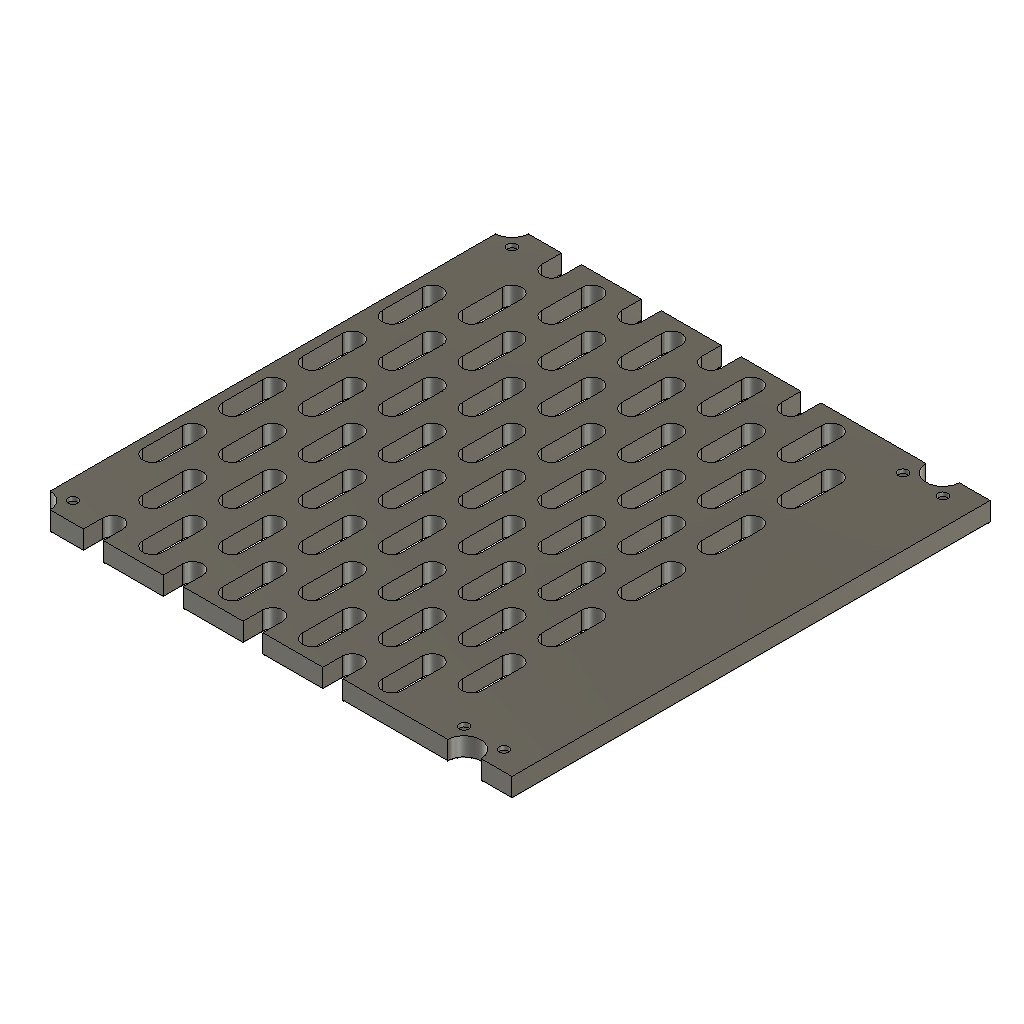
panel-right-edge-v03 (Autodesk Fusion 360 design; units mm, degrees)
part number: 2026-10-27-17-32-11-487
part number: 2026-10-27-17-32-12-104
Autodesk Fusion 360 part; units mm, degrees
sketch "01 Panel blank sketch" plane through (0, 0, 0) normal (0, 0, 1) x (1, 0, 0) in component "Panel right-edge"
  line L0 (0.1, 0.1) -> (119.9, 0.1)
  line L1 (119.9, 0.1) -> (119.9, 119.9)
  line L2 (119.9, 119.9) -> (0.1, 119.9)
  line L3 (0.1, 119.9) -> (0.1, 0.1)
  dimension "d57" = 0.1
  dimension "d58" = 0.1
  dimension "d59" = 119.8
  dimension "d60" = 119.8
  constraint horizontal L0
  constraint vertical L1
  constraint horizontal L2
  constraint vertical L3
  measures "d57" horizontal distance of origin L0.start
  measures "d58" vertical distance of origin L0.start
  measures "d59" horizontal distance of L0.start L0.end
  measures "d60" vertical distance of L0.end L1.end
extrude "01 Panel blank" add sketch "01 Panel blank sketch" along normal blind 5 in component "Panel right-edge"
sketch "03 A main constrained seed" plane through (0, 0, 0) normal (0, 0, 1) x (1, 0, 0) in component "Panel right-edge"
  line L0 (27.5, 5) -> (27.5, 15)
  arc A0 (27.5, 15) -> (22.5, 15) centre (25, 15) ccw
  line L1 (22.5, 15) -> (22.5, 5)
  arc A1 (22.5, 5) -> (27.5, 5) centre (25, 5) ccw
  line L2 (25, 5) -> (25, 15) construction
  line L3 (25, 5) -> (35, 5) construction
  dimension "d63" = 5
  dimension "d64" = 10
  dimension "d65" = 90
  dimension "d66" = 10
  dimension "d67" = 25
  dimension "d68" = 5
  constraint tangent L0 A0
  constraint tangent A0 L1
  constraint tangent L1 A1
  constraint tangent L0 A1
  constraint parallel L0 L1
  constraint horizontal L3
  measures "d63" diameter of A0
  measures "d64" distance of A1.centre A0.centre
  measures "d65" angle of L2 L3
  measures "d66" horizontal distance of A1.centre L3.end
  measures "d67" horizontal distance of origin A1.centre
  measures "d68" vertical distance of origin A1.centre
extrude "03 A main through cut" cut sketch "03 A main constrained seed" along normal blind 5 in component "Panel right-edge"
pattern_linear "03 A main lattice" count 4 spacing 20 along (1, 0, 0) count 6 spacing 20 along (0, 1, 0) of "03 A main through cut" in component "Panel right-edge"
sketch "04 A end strip constrained seed" plane through (0, 0, 0) normal (0, 0, 1) x (1, 0, 0) in component "Panel right-edge"
  line L0 (7.5, 25) -> (7.5, 35)
  arc A0 (7.5, 35) -> (2.5, 35) centre (5, 35) ccw
  line L1 (2.5, 35) -> (2.5, 25)
  arc A1 (2.5, 25) -> (7.5, 25) centre (5, 25) ccw
  line L2 (5, 25) -> (5, 35) construction
  line L3 (5, 25) -> (15, 25) construction
  dimension "d75" = 5
  dimension "d76" = 10
  dimension "d77" = 90
  dimension "d78" = 10
  dimension "d79" = 5
  dimension "d80" = 25
  constraint tangent L0 A0
  constraint tangent A0 L1
  constraint tangent L1 A1
  constraint tangent L0 A1
  constraint parallel L0 L1
  constraint horizontal L3
  measures "d75" diameter of A0
  measures "d76" distance of A1.centre A0.centre
  measures "d77" angle of L2 L3
  measures "d78" horizontal distance of A1.centre L3.end
  measures "d79" horizontal distance of origin A1.centre
  measures "d80" vertical distance of origin A1.centre
extrude "04 A end strip through cut" cut sketch "04 A end strip constrained seed" along normal blind 5 in component "Panel right-edge"
pattern_linear "04 A end strip lattice" count 1 spacing 20 along (1, 0, 0) count 4 spacing 20 along (0, 1, 0) of "04 A end strip through cut" in component "Panel right-edge"
sketch "05 B main constrained seed" plane through (0, 0, 0) normal (0, 0, 1) x (1, 0, 0) in component "Panel right-edge"
  line L0 (17.5, -5) -> (17.5, 5)
  arc A0 (17.5, 5) -> (12.5, 5) centre (15, 5) ccw
  line L1 (12.5, 5) -> (12.5, -5)
  arc A1 (12.5, -5) -> (17.5, -5) centre (15, -5) ccw
  line L2 (15, -5) -> (15, 5) construction
  line L3 (15, -5) -> (25, -5) construction
  dimension "d87" = 5
  dimension "d88" = 10
  dimension "d89" = 90
  dimension "d90" = 10
  dimension "d91" = 15
  dimension "d92" = 5
  constraint tangent L0 A0
  constraint tangent A0 L1
  constraint tangent L1 A1
  constraint tangent L0 A1
  constraint parallel L0 L1
  constraint horizontal L3
  measures "d87" diameter of A0
  measures "d88" distance of A1.centre A0.centre
  measures "d89" angle of L2 L3
  measures "d90" horizontal distance of A1.centre L3.end
  measures "d91" horizontal distance of origin A1.centre
  measures "d92" vertical distance of origin A1.centre
extrude "05 B main through cut" cut sketch "05 B main constrained seed" along normal blind 5 in component "Panel right-edge"
pattern_linear "05 B main lattice" count 4 spacing 20 along (1, 0, 0) count 7 spacing 20 along (0, 1, 0) of "05 B main through cut" in component "Panel right-edge"
sketch "06 B end strip constrained seed" plane through (0, 0, 0) normal (0, 0, 1) x (1, 0, 0) in component "Panel right-edge"
  line L0 (97.5, 15) -> (97.5, 25)
  arc A0 (97.5, 25) -> (92.5, 25) centre (95, 25) ccw
  line L1 (92.5, 25) -> (92.5, 15)
  arc A1 (92.5, 15) -> (97.5, 15) centre (95, 15) ccw
  line L2 (95, 15) -> (95, 25) construction
  line L3 (95, 15) -> (105, 15) construction
  dimension "d99" = 5
  dimension "d100" = 10
  dimension "d101" = 90
  dimension "d102" = 10
  dimension "d103" = 95
  dimension "d104" = 15
  constraint tangent L0 A0
  constraint tangent A0 L1
  constraint tangent L1 A1
  constraint tangent L0 A1
  constraint parallel L0 L1
  constraint horizontal L3
  measures "d99" diameter of A0
  measures "d100" distance of A1.centre A0.centre
  measures "d101" angle of L2 L3
  measures "d102" horizontal distance of A1.centre L3.end
  measures "d103" horizontal distance of origin A1.centre
  measures "d104" vertical distance of origin A1.centre
extrude "06 B end strip through cut" cut sketch "06 B end strip constrained seed" along normal blind 5 in component "Panel right-edge"
pattern_linear "06 B end strip lattice" count 1 spacing 20 along (1, 0, 0) count 5 spacing 20 along (0, 1, 0) of "06 B end strip through cut" in component "Panel right-edge"
sketch "07 Shared node clearance sketch" plane through (0, 0, 0) normal (0, 0, 1) x (1, 0, 0) in component "Panel right-edge"
  circle A0 centre (0, 0) radius 4.2
  dimension "d111" = 8.4
  constraint coincident A0.centre origin
  measures "d111" diameter of A0
extrude "07 Shared node clearance" cut sketch "07 Shared node clearance sketch" along normal blind 5 in component "Panel right-edge"
sketch "07 Shared node clearance sketch (1)" plane through (0, 0, 0) normal (0, 0, 1) x (1, 0, 0) in component "Panel right-edge"
  circle A0 centre (0, 120) radius 4.2
  dimension "d114" = 120
  dimension "d115" = 8.4
  constraint vertical origin A0.centre
  measures "d114" vertical distance of origin A0.centre
  measures "d115" diameter of A0
extrude "07 Shared node clearance (1)" cut sketch "07 Shared node clearance sketch (1)" along normal blind 5 in component "Panel right-edge"
sketch "07 Shared node clearance sketch (2)" plane through (0, 0, 0) normal (0, 0, 1) x (1, 0, 0) in component "Panel right-edge"
  circle A0 centre (108, 0) radius 4.2
  dimension "d118" = 108
  dimension "d119" = 8.4
  constraint horizontal origin A0.centre
  measures "d118" horizontal distance of origin A0.centre
  measures "d119" diameter of A0
extrude "07 Shared node clearance (2)" cut sketch "07 Shared node clearance sketch (2)" along normal blind 5 in component "Panel right-edge"
sketch "07 Shared node clearance sketch (3)" plane through (0, 0, 0) normal (0, 0, 1) x (1, 0, 0) in component "Panel right-edge"
  circle A0 centre (108, 120) radius 4.2
  dimension "d122" = 108
  dimension "d123" = 120
  dimension "d124" = 8.4
  measures "d122" horizontal distance of origin A0.centre
  measures "d123" vertical distance of origin A0.centre
  measures "d124" diameter of A0
extrude "07 Shared node clearance (3)" cut sketch "07 Shared node clearance sketch (3)" along normal blind 5 in component "Panel right-edge"
fillet "08 Rounded slot entrances and face edges" radius 0.4 2 faces at (112.4333, 58.3333, 0) (112.4333, 58.3333, 0) in component "Panel right-edge"
ref_plane "WorkPlane1" through (0, 0, 5) normal (0, 0, 1) x (1, 0, 0) in component "Panel right-edge"
sketch "09 Blind rear key socket sketch" plane through (0, 0, 5) normal (0, 0, 1) x (1, 0, 0) in component "Panel right-edge"
  circle A0 centre (5, 80) radius 1.7
  dimension "d131" = 5
  dimension "d132" = 80
  dimension "d133" = 3.4
  measures "d131" horizontal distance of origin A0.centre
  measures "d132" vertical distance of origin A0.centre
  measures "d133" diameter of A0
ref_plane "WorkPlane2" through (0, 0, 5) normal (0, 0, 1) x (1, 0, 0) in component "Panel right-edge"
sketch "09 Blind rear key socket sketch (1)" plane through (0, 0, 5) normal (0, 0, 1) x (1, 0, 0) in component "Panel right-edge"
  circle A0 centre (70, 5) radius 1.7
  dimension "d138" = 70
  dimension "d139" = 5
  dimension "d140" = 3.4
  measures "d138" horizontal distance of origin A0.centre
  measures "d139" vertical distance of origin A0.centre
  measures "d140" diameter of A0
ref_plane "WorkPlane3" through (0, 0, 5) normal (0, 0, 1) x (1, 0, 0) in component "Panel right-edge"
sketch "09 Blind rear key socket sketch (2)" plane through (0, 0, 5) normal (0, 0, 1) x (1, 0, 0) in component "Panel right-edge"
  circle A0 centre (70, 115) radius 1.7
  dimension "d145" = 70
  dimension "d146" = 115
  dimension "d147" = 3.4
  measures "d145" horizontal distance of origin A0.centre
  measures "d146" vertical distance of origin A0.centre
  measures "d147" diameter of A0
ref_plane "WorkPlane4" through (0, 0, 5) normal (0, 0, 1) x (1, 0, 0) in component "Panel right-edge"
sketch "10 Node register socket sketch" plane through (0, 0, 5) normal (0, 0, 1) x (1, 0, 0) in component "Panel right-edge"
  circle A0 centre (5, 5) radius 1.2
  dimension "d152" = 5
  dimension "d153" = 5
  dimension "d154" = 2.4
  measures "d152" horizontal distance of origin A0.centre
  measures "d153" vertical distance of origin A0.centre
  measures "d154" diameter of A0
extrude "10 Node register socket" cut sketch "10 Node register socket sketch" against normal blind 1 in component "Panel right-edge"
ref_plane "WorkPlane5" through (0, 0, 5) normal (0, 0, 1) x (1, 0, 0) in component "Panel right-edge"
sketch "10 Node register socket sketch (1)" plane through (0, 0, 5) normal (0, 0, 1) x (1, 0, 0) in component "Panel right-edge"
  circle A0 centre (5, 115) radius 1.2
  dimension "d159" = 5
  dimension "d160" = 115
  dimension "d161" = 2.4
  measures "d159" horizontal distance of origin A0.centre
  measures "d160" vertical distance of origin A0.centre
  measures "d161" diameter of A0
extrude "10 Node register socket (1)" cut sketch "10 Node register socket sketch (1)" against normal blind 1 in component "Panel right-edge"
ref_plane "WorkPlane6" through (0, 0, 5) normal (0, 0, 1) x (1, 0, 0) in component "Panel right-edge"
sketch "10 Node register socket sketch (2)" plane through (0, 0, 5) normal (0, 0, 1) x (1, 0, 0) in component "Panel right-edge"
  circle A0 centre (103, 5) radius 1.2
  dimension "d166" = 103
  dimension "d167" = 5
  dimension "d168" = 2.4
  measures "d166" horizontal distance of origin A0.centre
  measures "d167" vertical distance of origin A0.centre
  measures "d168" diameter of A0
extrude "10 Node register socket (2)" cut sketch "10 Node register socket sketch (2)" against normal blind 1 in component "Panel right-edge"
ref_plane "WorkPlane7" through (0, 0, 5) normal (0, 0, 1) x (1, 0, 0) in component "Panel right-edge"
sketch "10 Node register socket sketch (3)" plane through (0, 0, 5) normal (0, 0, 1) x (1, 0, 0) in component "Panel right-edge"
  circle A0 centre (113, 5) radius 1.2
  dimension "d173" = 113
  dimension "d174" = 5
  dimension "d175" = 2.4
  measures "d173" horizontal distance of origin A0.centre
  measures "d174" vertical distance of origin A0.centre
  measures "d175" diameter of A0
extrude "10 Node register socket (3)" cut sketch "10 Node register socket sketch (3)" against normal blind 1 in component "Panel right-edge"
ref_plane "WorkPlane8" through (0, 0, 5) normal (0, 0, 1) x (1, 0, 0) in component "Panel right-edge"
sketch "10 Node register socket sketch (4)" plane through (0, 0, 5) normal (0, 0, 1) x (1, 0, 0) in component "Panel right-edge"
  circle A0 centre (103, 115) radius 1.2
  dimension "d180" = 103
  dimension "d181" = 115
  dimension "d182" = 2.4
  measures "d180" horizontal distance of origin A0.centre
  measures "d181" vertical distance of origin A0.centre
  measures "d182" diameter of A0
extrude "10 Node register socket (4)" cut sketch "10 Node register socket sketch (4)" against normal blind 1 in component "Panel right-edge"
ref_plane "WorkPlane9" through (0, 0, 5) normal (0, 0, 1) x (1, 0, 0) in component "Panel right-edge"
sketch "10 Node register socket sketch (5)" plane through (0, 0, 5) normal (0, 0, 1) x (1, 0, 0) in component "Panel right-edge"
  circle A0 centre (113, 115) radius 1.2
  dimension "d187" = 113
  dimension "d188" = 115
  dimension "d189" = 2.4
  measures "d187" horizontal distance of origin A0.centre
  measures "d188" vertical distance of origin A0.centre
  measures "d189" diameter of A0
extrude "10 Node register socket (5)" cut sketch "10 Node register socket sketch (5)" against normal blind 1 in component "Panel right-edge"
component "Panel right-edge" placed x (1, 0, 0) y (0, 1, 0) z (0, 0, 1) at (0, 0, 0)
equation "columns = 6" comment "Even integer 4..14; each cell is 20 mm"
equation "rows = 6" comment "Even integer 4..14"
equation "pitch = 20 mm" comment "Keep for dense SKADIS compatible lattice"
equation "panelWidth = columns * pitch" comment "Nominal module pitch X"
equation "panelHeight = rows * pitch" comment "Nominal module pitch Y"
equation "seamGap = 0.2 mm" comment "Physical envelope shrinks around fixed lattice"
equation "boardThickness = 5 mm" comment "Fit-test with real hooks"
equation "slotWidth = 5 mm" comment "Minimum throat width"
equation "slotHeight = 15 mm" comment "Minimum throat height"
equation "entryRadius = 0.4 mm" comment "Front slot and perimeter edge rounding"
equation "cornerRadius = 6 mm" comment "Plan-view panel corner rounding"
equation "hookClearance = 10 mm" comment "PROVISIONAL: board rear to front of extrusion"
equation "frameZ = boardThickness + hookClearance" comment "Front extrusion datum"
equation "mountInset = 12 mm" comment "Exterior node inset from outside module edge"
equation "mountBore = 8.4 mm" comment "Clearance around 8 mm metal shoulder"
equation "capDiameter = 18 mm" comment "Visible decorative mounting disk"
equation "capThickness = 5 mm" comment "Metal clamping cap / washer"
equation "seatThickness = 2 mm" comment "Printed rear bearing washer"
equation "screwDiameter = 5 mm" comment "Nominal M5 reference, threads omitted"
equation "screwClearance = 5.5 mm" comment "Cap and spacer bore"
equation "keyWidth = 4 mm" comment "Registration key corridor width"
equation "keyThickness = 2 mm" comment "Rear removable key body"
equation "keyPegDiameter = 3 mm" comment "Rear locating peg"
equation "keySocketDiameter = 3.4 mm" comment "0.2 mm radial starting fit"
equation "keyPegHeight = 0.8 mm" comment "Peg penetration"
equation "keySocketDepth = 1 mm" comment "Blind locating pocket"
equation "profileMouth = 6.28 mm" comment "User measured mouth"
equation "profileCavity = 11 mm" comment "User measured widest cavity"
equation "profileDepth = 6.2 mm" comment "User measured face-to-floor depth"
equation "profileFloor = 5.7 mm" comment "User estimate, lower confidence"
equation "profileLip = 1.5 mm" comment "Unmeasured; tentative comparable catalog value"
equation "profileTaperStart = profileDepth - ( profileCavity - profileFloor ) / 2" comment "Assumed 45-degree inner slopes"
equation "profileBore = 5 mm" comment "Unmeasured central bore, reference only"
equation "nutWidth = 8.8 mm" comment "Provisional low-profile METAL T-nut envelope, not old rectangular carrier"
equation "nutLength = 12 mm" comment "End-loaded anti-rotation metal nut envelope"
equation "nutThickness = 2.7 mm" comment "Thin nut reference; fit/load still unverified"
equation "jointLeg = 18 mm" comment "In-bay angle footprint"
equation "jointThickness = 3 mm" comment "Metal bracket thickness"
equation "jointDepth = 16 mm" comment "Bracket depth within 20 mm rail"
equation "sideScrewLength = 8 mm" comment "M5x8 reference; check against actual bracket and nut"
equation "registerPin = 2 mm" comment "Node-seat locating pins"
equation "registerSocket = 2.4 mm" comment "Starting printed locating clearance"
equation "registerPinHeight = 0.8 mm" comment "Pin into rear socket"
equation "registerSocketDepth = 1 mm" comment "Blind panel socket"
equation "registerOffset = 5 mm" comment "Four pegs at node +/- offset"
equation "wallTabHeight = 24 mm" comment "Tab along extrusion"
equation "wallTabReach = 22 mm" comment "Tab into open bay"
equation "wallAnchorClearance = 6.5 mm" comment "Placeholder wall anchor interface"
equation "wallShim = 0 mm" comment "Only actual leveling shims; no designed rear air gap"
equation "wallDriverDiameter = 12 mm" comment "Clear tool envelope in open bays"
equation "keyDriverDiameter = 5 mm" comment "Short hex-key working-leg envelope"
equation "keyDriverReach = 20 mm" comment "Short hex-key working-leg reach"
equation "panelLeft = 0" comment "0 internal / 1 finished; full cell border and inset mounting"
equation "panelRight = 1" comment "0 internal / 1 finished; full cell border and inset mounting"
equation "panelBottom = 0" comment "0 internal / 1 finished; full cell border and inset mounting"
equation "panelTop = 0" comment "0 internal / 1 finished; full cell border and inset mounting"
equation "d57 = abs(( 0 mm ) + seamGap / 2)"
equation "d58 = abs(( 0 mm ) + seamGap / 2)"
equation "d59 = panelWidth - seamGap"
equation "d60 = panelHeight - seamGap"
equation "d61 = boardThickness"
equation "d63 = slotWidth"
equation "d64 = slotHeight - slotWidth"
equation "d66 = pitch / 2"
equation "d67 = abs(( 0 mm ) + pitch / 4 + pitch * ( panelLeft + 1 ))"
equation "d68 = abs(( ( 0 mm ) + pitch / 2 + pitch * panelBottom ) - ( slotHeight - slotWidth ) / 2)"
equation "d69 = boardThickness"
equation "d71 = columns - panelLeft - panelRight - 1"
equation "d72 = rows - panelBottom - panelTop"
equation "d73 = pitch"
equation "d74 = pitch"
equation "d75 = slotWidth"
equation "d76 = slotHeight - slotWidth"
equation "d78 = pitch / 2"
equation "d79 = abs(( 0 mm ) + pitch / 4 + pitch * panelLeft)"
equation "d80 = abs(( ( 0 mm ) + 3 * pitch / 2 + pitch * panelBottom ) - ( slotHeight - slotWidth ) / 2)"
equation "d81 = boardThickness"
equation "d84 = rows - panelBottom - panelTop - 2"
equation "d85 = pitch"
equation "d86 = pitch"
equation "d87 = slotWidth"
equation "d88 = slotHeight - slotWidth"
equation "d90 = pitch / 2"
equation "d91 = abs(( 0 mm ) + 3 * pitch / 4 + pitch * panelLeft)"
equation "d92 = abs(( ( 0 mm ) + pitch * panelBottom ) - ( slotHeight - slotWidth ) / 2)"
equation "d93 = boardThickness"
equation "d95 = columns - panelLeft - panelRight - 1"
equation "d96 = rows + 1 - panelBottom - panelTop"
equation "d97 = pitch"
equation "d98 = pitch"
equation "d99 = slotWidth"
equation "d100 = slotHeight - slotWidth"
equation "d102 = pitch / 2"
equation "d103 = abs(( 0 mm ) + panelWidth - pitch / 4 - pitch * panelRight)"
equation "d104 = abs(( ( 0 mm ) + pitch + pitch * panelBottom ) - ( slotHeight - slotWidth ) / 2)"
equation "d105 = boardThickness"
equation "d108 = rows - 1 - panelBottom - panelTop"
equation "d109 = pitch"
equation "d110 = pitch"
equation "d111 = mountBore"
equation "d112 = boardThickness"
equation "d114 = abs(( 0 mm ) + panelHeight - mountInset * panelTop)"
equation "d115 = mountBore"
equation "d116 = boardThickness"
equation "d118 = abs(( 0 mm ) + panelWidth - mountInset * panelRight)"
equation "d119 = mountBore"
equation "d120 = boardThickness"
equation "d122 = abs(( 0 mm ) + panelWidth - mountInset * panelRight)"
equation "d123 = abs(( 0 mm ) + panelHeight - mountInset * panelTop)"
equation "d124 = mountBore"
equation "d125 = boardThickness"
equation "d128 = entryRadius"
equation "d129 = boardThickness"
equation "d131 = abs(( 0 mm ) + pitch / 4)"
equation "d132 = abs(( 0 mm ) + panelHeight / 2 + pitch)"
equation "d133 = keySocketDiameter"
equation "d136 = boardThickness"
equation "d138 = abs(( 0 mm ) + panelWidth / 2 + pitch / 2)"
equation "d139 = abs(( 0 mm ) + pitch / 4)"
equation "d140 = keySocketDiameter"
equation "d143 = boardThickness"
equation "d145 = abs(( 0 mm ) + panelWidth / 2 + pitch / 2)"
equation "d146 = abs(( 0 mm ) + panelHeight - pitch / 4)"
equation "d147 = keySocketDiameter"
equation "d150 = boardThickness"
equation "d152 = abs(( 0 mm ) + mountInset * panelLeft + ( 1 ) * registerOffset)"
equation "d153 = abs(( 0 mm ) + mountInset * panelBottom + ( 1 ) * registerOffset)"
equation "d154 = registerSocket"
equation "d155 = -registerSocketDepth"
equation "d157 = boardThickness"
equation "d159 = abs(( 0 mm ) + mountInset * panelLeft + ( 1 ) * registerOffset)"
equation "d160 = abs(( 0 mm ) + panelHeight - mountInset * panelTop + ( -1 ) * registerOffset)"
equation "d161 = registerSocket"
equation "d162 = -registerSocketDepth"
equation "d164 = boardThickness"
equation "d166 = abs(( 0 mm ) + panelWidth - mountInset * panelRight + ( -1 ) * registerOffset)"
equation "d167 = abs(( 0 mm ) + mountInset * panelBottom + ( 1 ) * registerOffset)"
equation "d168 = registerSocket"
equation "d169 = -registerSocketDepth"
equation "d171 = boardThickness"
equation "d173 = abs(( 0 mm ) + panelWidth - mountInset * panelRight + ( 1 ) * registerOffset)"
equation "d174 = abs(( 0 mm ) + mountInset * panelBottom + ( 1 ) * registerOffset)"
equation "d175 = registerSocket"
equation "d176 = -registerSocketDepth"
equation "d178 = boardThickness"
equation "d180 = abs(( 0 mm ) + panelWidth - mountInset * panelRight + ( -1 ) * registerOffset)"
equation "d181 = abs(( 0 mm ) + panelHeight - mountInset * panelTop + ( -1 ) * registerOffset)"
equation "d182 = registerSocket"
equation "d183 = -registerSocketDepth"
equation "d185 = boardThickness"
equation "d187 = abs(( 0 mm ) + panelWidth - mountInset * panelRight + ( 1 ) * registerOffset)"
equation "d188 = abs(( 0 mm ) + panelHeight - mountInset * panelTop + ( -1 ) * registerOffset)"
equation "d189 = registerSocket"
equation "d190 = -registerSocketDepth"
named bodies: "Panel right-edge"
